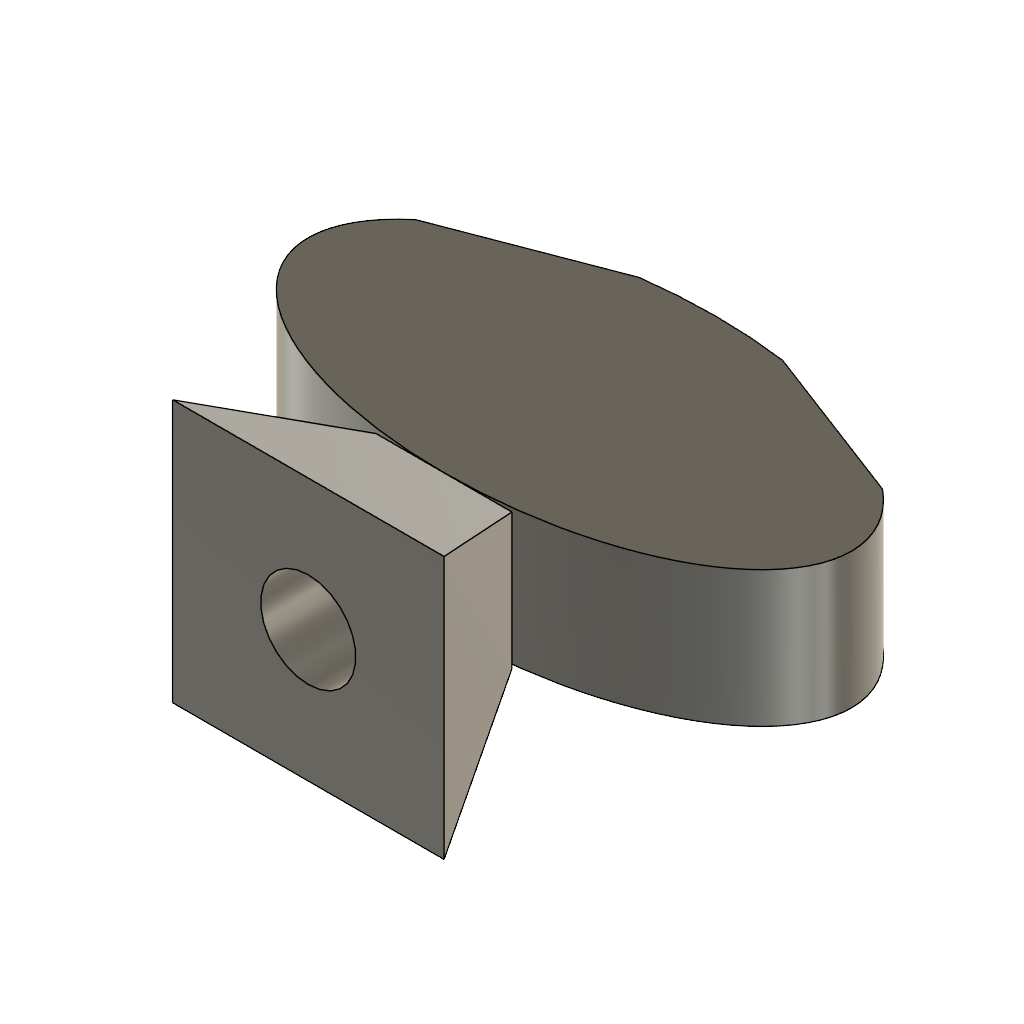
pieza_6 (Autodesk Fusion 360 design; units mm, degrees)
part number: 2026-11-10-20-47-24-551
Autodesk Fusion 360 part; units mm, degrees
sketch "Boceto1" plane through (0, 0, 0) normal (0, 0, 1) x (1, 0, 0)
  line L0 (-17.89, 4.4707) -> (-4.8486, 9.7017)
  line L1 (4.8486, 9.7017) -> (17.89, 4.4707)
  line L2 (-4.694, -9.7207) -> (-10, -20)
  line L3 (-10, -20) -> (10, -20)
  line L4 (10, -20) -> (5.4465, -9.6221)
  ellipse E0 centre (0, 0) end of major axis (20, 0) minor radius 10 (5.4465, -9.6221) -> (-4.694, -9.7207) ccw
  dimension "d1" = 40
  dimension "d2" = 20
  constraint coincident E0.centre origin
  constraint coincident L0.start E0
  constraint coincident L0.end E0
  constraint coincident L1.start E0
  constraint coincident L1.end E0
  constraint horizontal L3
  measures "d1" distance of E0
  measures "d2" distance of E0
sketch "Boceto2" plane through (0, 0, 0) normal (0, 0, 1) x (1, 0, 0)
  ellipse E0 centre (0, 0) end of major axis (20, 0) minor radius 10
  line L0 (-20, 0) -> (20, 0) construction
  line L1 (0, -10) -> (0, 10) construction
  line L2 (-17.2004, 5.1026) -> (-5.2912, 9.6437)
  line L3 (5.2912, 9.6437) -> (17.2004, 5.1026)
  dimension "d5" = 40
  dimension "d6" = 20
  constraint coincident E0 L0.start
  constraint coincident E0 L0.end
  constraint coincident E0 L1.start
  constraint coincident E0 L1.end
  constraint coincident E0.centre origin
  constraint horizontal L0
  constraint coincident E0 L2.start
  constraint coincident E0 L2.end
  constraint coincident E0 L3.start
  constraint coincident E0 L3.end
  measures "d5" distance of E0
  measures "d6" distance of E0
extrude "Extruir2" add sketch "Boceto2" along normal blind 10 contours E0 L2 L3 makes body 1
sketch "Boceto3" plane through (0, 0, 10) normal (0, 0, 1) x (-1, 0, 0)
  ellipse E0 centre (0, 0) end of major axis (-20, 0) minor radius 10 (17.2004, -5.1026) -> (-17.2004, -5.1026) ccw
  line L0 (-17.2004, -5.1026) -> (-5.2912, -9.6437)
  ellipse E1 centre (0, 0) end of major axis (-20, 0) minor radius 10 (-5.2912, -9.6437) -> (5.2912, -9.6437) ccw
  line L1 (5.2912, -9.6437) -> (17.2004, -5.1026)
  line L2 (5, 10) -> (10, 20)
  line L3 (10, 20) -> (-10, 20)
  line L4 (-10, 20) -> (-5, 10)
  line L5 (-5, 10) -> (5, 10)
  constraint horizontal L3
  constraint parallel L3 L5
extrude "Extruir3" add sketch "Boceto3" along normal blind 10 separate body contours L2 L3 L4 L5 makes body 2
move_body "Desplazar1" bodies 2 to x (1, 0, 0) y (0, 1, 0) z (0, 0, 1) at (0, 0, -10)
draft "Desmoldeo1" angle 25 neutral plane through (5, -10, 0) pull (0, 1, 0) 1 faces at (0, -16.6667, 10) on bodies 2
draft "Desmoldeo2" angle 25 neutral plane through (5, -10, 0) pull (0, 1, 0) 1 faces at (0, -16.6667, 0) on bodies 2
combine "Combinar1" operation add target body 2 tool bodies 1
hole "Agujero1" at (0, -20, 5) direction (0, 1, 0) diameter 7 depth 8 tip angle 180 bodies 2
hole "Agujero2" at (-0.1414, 9.9998, 4.6978) direction (0.003535, -0.999994, 0) diameter 7 depth 8 tip angle 180 bodies 2
